Autodesk Fusion 360 part; units mm, degrees
(part 2 of 2)
ref_plane "WorkPlane2" through (-5.075, 0, 0) normal (1, 0, 0) x (0, 1, 0) in component "Factory radio brackets (placeholder)"
sketch "Sketch2 (13)" plane through (-5.075, 0, 0) normal (1, 0, 0) x (0, 0, -1) in component "Factory radio brackets (placeholder)"
  line L0 (42, 104.75) -> (34, 104.75)
  arc A0 (34, 110.25) -> (34, 104.75) centre (34, 107.5) ccw
  line L1 (34, 110.25) -> (42, 110.25)
  arc A1 (42, 104.75) -> (42, 110.25) centre (42, 107.5) ccw
  line L2 (42, 129.75) -> (34, 129.75)
  arc A2 (34, 135.25) -> (34, 129.75) centre (34, 132.5) ccw
  line L3 (34, 135.25) -> (42, 135.25)
  arc A3 (42, 129.75) -> (42, 135.25) centre (42, 132.5) ccw
  line L4 (42, 169.75) -> (34, 169.75)
  arc A4 (34, 175.25) -> (34, 169.75) centre (34, 172.5) ccw
  line L5 (34, 175.25) -> (42, 175.25)
  arc A5 (42, 169.75) -> (42, 175.25) centre (42, 172.5) ccw
  line L6 (42, 194.75) -> (34, 194.75)
  arc A6 (34, 200.25) -> (34, 194.75) centre (34, 197.5) ccw
  line L7 (34, 200.25) -> (42, 200.25)
  arc A7 (42, 194.75) -> (42, 200.25) centre (42, 197.5) ccw
extrude "Extrude2'''" cut sketch "Sketch2 (13)" along normal mid plane 3.6 bodies 18 in component "Factory radio brackets (placeholder)"
ref_plane "WorkPlane3" through (176.525, 0, 0) normal (1, 0, 0) x (0, 1, 0) in component "Factory radio brackets (placeholder)"
sketch "Sketch3 (10)" plane through (176.525, 0, 0) normal (1, 0, 0) x (0, 0, -1) in component "Factory radio brackets (placeholder)"
  line L0 (70, 87) -> (70, 218)
  arc A0 (70, 218) -> (68, 220) centre (68, 218) ccw
  line L1 (68, 220) -> (20, 220)
  arc A1 (20, 220) -> (18, 218) centre (20, 218) ccw
  line L2 (18, 218) -> (18, 87)
  arc A2 (18, 87) -> (20, 85) centre (20, 87) ccw
  line L3 (20, 85) -> (68, 85)
  arc A3 (68, 85) -> (70, 87) centre (68, 87) ccw
extrude "Extrude3" add sketch "Sketch3 (10)" along normal mid plane 1.6 separate body makes body 19 in component "Factory radio brackets (placeholder)"
ref_plane "WorkPlane4" through (176.525, 0, 0) normal (1, 0, 0) x (0, 1, 0) in component "Factory radio brackets (placeholder)"
sketch "Sketch4 (10)" plane through (176.525, 0, 0) normal (1, 0, 0) x (0, 0, -1) in component "Factory radio brackets (placeholder)"
  line L0 (42, 104.75) -> (34, 104.75)
  arc A0 (34, 110.25) -> (34, 104.75) centre (34, 107.5) ccw
  line L1 (34, 110.25) -> (42, 110.25)
  arc A1 (42, 104.75) -> (42, 110.25) centre (42, 107.5) ccw
  line L2 (42, 129.75) -> (34, 129.75)
  arc A2 (34, 135.25) -> (34, 129.75) centre (34, 132.5) ccw
  line L3 (34, 135.25) -> (42, 135.25)
  arc A3 (42, 129.75) -> (42, 135.25) centre (42, 132.5) ccw
  line L4 (42, 169.75) -> (34, 169.75)
  arc A4 (34, 175.25) -> (34, 169.75) centre (34, 172.5) ccw
  line L5 (34, 175.25) -> (42, 175.25)
  arc A5 (42, 169.75) -> (42, 175.25) centre (42, 172.5) ccw
  line L6 (42, 194.75) -> (34, 194.75)
  arc A6 (34, 200.25) -> (34, 194.75) centre (34, 197.5) ccw
  line L7 (34, 200.25) -> (42, 200.25)
  arc A7 (42, 194.75) -> (42, 200.25) centre (42, 197.5) ccw
extrude "Extrude4" cut sketch "Sketch4 (10)" along normal mid plane 3.6 bodies 19 in component "Factory radio brackets (placeholder)"
component "Dash panel" placed x (1, 0, 0) y (0, 1, 0) z (0, 0, 1) at (0, 0, 0)
component "Screen carrier" placed x (1, 0, 0) y (0, 1, 0) z (0, 0, 1) at (0, 0, 0)
component "Volume knob" placed x (1, 0, 0) y (0, 1, 0) z (0, 0, 1) at (0, 0, 0)
component "Adapter plate lower left" placed x (1, 0, 0) y (0, 1, 0) z (0, 0, 1) at (0, 0, 0)
component "Adapter plate upper left" placed x (1, 0, 0) y (0, 1, 0) z (0, 0, 1) at (0, 0, 0)
component "Adapter plate lower right" placed x (1, 0, 0) y (0, 1, 0) z (0, 0, 1) at (0, 0, 0)
component "Adapter plate upper right" placed x (1, 0, 0) y (0, 1, 0) z (0, 0, 1) at (0, 0, 0)
component "Pi case" placed x (1, 0, 0) y (0, 1, 0) z (0, 0, 1) at (0, 0, 0)
component "Amp plate" placed x (1, 0, 0) y (0, 1, 0) z (0, 0, 1) at (0, 0, 0)
component "Screen (reference)" placed x (1, 0, 0) y (0, 1, 0) z (0, 0, 1) at (0, 0, 0)
component "Raspberry Pi 5 + DAC (reference)" placed x (1, 0, 0) y (0, 1, 0) z (0, 0, 1) at (0, 0, 0)
component "Amp (reference)" placed x (1, 0, 0) y (0, 1, 0) z (0, 0, 1) at (0, 0, 0)
component "Mean Well RSD-30G-5 (reference)" placed x (1, 0, 0) y (0, 1, 0) z (0, 0, 1) at (0, 0, 0)
component "Climate controls (space)" placed x (1, 0, 0) y (0, 1, 0) z (0, 0, 1) at (0, 0, 0)
component "Factory radio brackets (placeholder)" placed x (1, 0, 0) y (0, 1, 0) z (0, 0, 1) at (0, 0, 0)
equation "BajaCaseVersion = 7" comment "Marks this design as the Baja dash case; the script rebuilds it in place"
equation "OpeningWidth = 171.45 mm" comment "MEASURED (Caleb): bezel opening width, 6 3/4 in"
equation "OpeningHeight = 222.25 mm" comment "MEASURED (Caleb): bezel opening height, 8 3/4 in"
equation "CornerRadiusTopLeft = 15 mm" comment "MEASURED (Caleb, re-measured after the first test print)"
equation "CornerRadiusTopRight = 3 mm" comment "MEASURED (Caleb, re-measured after the first test print)"
equation "CornerClearance = 0.5 mm" comment "DESIGN: the panel's top corners are this much rounder than the opening's, so they never bind"
equation "ClimateGap = 82.55 mm" comment "MEASURED (Caleb): the climate controls fill the bottom 3 1/4 in of the opening (6 3/4 in wide)"
equation "BezelReturnDepth = 20 mm" comment "UNKNOWN: how far the bezel walls reach behind the panel; the adapters step out behind them"
equation "BracketSeparation = 180 mm" comment "ESTIMATED: inside face to inside face of the factory brackets (radio width); 180 is a common DIN width, not verified for the Baja"
equation "FactoryBracketUpperY = 185 mm" comment "UNKNOWN: middle of the upper adapter screws, above the bottom of the opening"
equation "FactoryBracketLowerY = 120 mm" comment "UNKNOWN: middle of the lower adapter screws, above the bottom of the opening"
equation "FactoryBracketHoleSpacing = 25 mm" comment "UNKNOWN: up-and-down spacing of the two screws each adapter takes"
equation "FactoryHoleDiameter = 5.5 mm" comment "ESTIMATED: M5 clearance; Subaru screw 045005160 reads as M5 x 16 by its part-number pattern"
equation "FactoryBracketThickness = 1.6 mm" comment "UNKNOWN: steel thickness of the factory bracket (reference model only)"
equation "PanelThickness = 12.7 mm" comment "DESIGN (Caleb): 1/2 in"
equation "FitGap = 0 mm" comment "DESIGN: 0 = exactly the measured opening; add 0.2-0.4 per side if the test print is tight"
equation "PanelBottomRadius = 0 mm" comment "MEASURED (Caleb): the opening's bottom corners are square"
equation "FrameEdgeDepth = 10 mm" comment "MEASURED (Caleb): the silver frame is 10 mm thick at the opening's edge; the panel's front part is this deep"
equation "LipSide = 3 mm" comment "MEASURED (Caleb): behind the frame the panel is this much wider on the left and right, so the frame holds it"
equation "LipTop = 3 mm" comment "MEASURED (Caleb): the same 3 mm lip along the top edge"
equation "LipRadiusTopLeft = 0 mm" comment "DESIGN (Caleb): the lip's top-left corner is square; the top-right follows the rounded corner"
equation "AdapterPlateThickness = 4 mm" comment "DESIGN: adapter plate wall (ASA, carries the M5 screws)"
equation "AdapterHeight = 50 mm" comment "DESIGN: height of each of the four adapter plates"
equation "AdapterSideLength = 40 mm" comment "DESIGN: front-to-back length of the slotted side wall"
equation "AdapterSlotLength = 24 mm" comment "DESIGN: front-to-back adjustment in the side slots"
equation "ScreenWidth = 194 mm" comment "VERIFIED: Waveshare 8DP-CAPLCD drawing; Caleb's caliper check of the holes matches it"
equation "ScreenHeight = 119 mm" comment "VERIFIED: Waveshare 8DP-CAPLCD drawing"
equation "ScreenDepth = 4.8 mm" comment "VERIFIED: glass + LCD, Waveshare drawing"
equation "ScreenBackDepth = 11.39 mm" comment "VERIFIED: glass front to the back of the mounting nuts, Waveshare drawing"
equation "ScreenMountHoleSpacing = 58 mm" comment "VERIFIED: Raspberry Pi hole pattern, side to side (Waveshare drawing)"
equation "ScreenMountHoleSpacingV = 49 mm" comment "VERIFIED: Raspberry Pi hole pattern, up and down"
equation "ScreenMountOffsetX = -12.21 mm" comment "VERIFIED: hole pattern centre is 12.2 mm left of the glass centre, seen from the front (Waveshare drawing; Caleb measured 12.8)"
equation "ScreenMountOffsetY = -3.21 mm" comment "VERIFIED: 3.2 mm below the glass centre (Waveshare drawing; Caleb measured 3.9)"
equation "ScreenOverhangTop = 5.5 mm" comment "DESIGN (Caleb): top of the screen stands this far above the opening"
equation "ScreenStandoffHeight = 6 mm" comment "DESIGN (Caleb): posts from the panel face to the back of the screen, 6 at most"
equation "ScreenPostDiameter = 8 mm" comment "DESIGN: the carrier's screen posts"
equation "DisplayTiltAngle = 0 deg" comment "DESIGN: + leans the screen back by shortening the top posts; keep it small (0 to 4)"
equation "CableClearance = 6 mm" comment "DESIGN: room around the plugs in the panel notch"
equation "PlugAreaLeft = -40 mm" comment "VERIFIED: left end of the USB-C/HDMI/USB sockets from the glass centre, seen from the front (Waveshare drawing)"
equation "PlugAreaRight = 14 mm" comment "VERIFIED: right end of the sockets from the glass centre (Waveshare drawing)"
equation "PlugAreaBottom = 33 mm" comment "VERIFIED: the board's top edge, where the plugs go in, above the glass centre (Waveshare drawing; HDMI faces up, Caleb)"
equation "KnobX = 25 mm" comment "DESIGN (Caleb): driver side"
equation "KnobY = 93.3 mm" comment "DESIGN: centred between the climate controls and the bottom of the screen"
equation "KnobDiameter = 19 mm" comment "DESIGN: 3/4 in; the strip between the climate controls and the screen is about 24.5 mm tall"
equation "KnobHeight = 18 mm" comment "DESIGN: fits a 15 or 20 mm encoder shaft"
equation "EncoderWall = 2.5 mm" comment "DESIGN: panel left in front of the encoder so its nut reaches"
equation "EncoderCollarHole = 7.4 mm" comment "ESTIMATED: EC11 threaded collar is M7"
equation "EncoderPocket = 15 mm" comment "MEASURED (Caleb): square pocket for the encoder body, 15 x 15"
equation "ShaftDiameter = 6.1 mm" comment "MEASURED (Caleb): 6 mm shaft"
equation "ShaftFlat = 4.6 mm" comment "ESTIMATED: D shaft, 4.5 mm across the flat"
equation "PiX = 43.2 mm" comment "DESIGN: left edge of the Pi board"
equation "PiY = 110 mm" comment "DESIGN: bottom edge of the Pi board"
equation "PiStandoffHeight = 6 mm" comment "DESIGN"
equation "PiCaseWall = 2 mm" comment "DESIGN: wall of the Pi case"
equation "PiCaseHeight = 25 mm" comment "DESIGN: wall height from the case floor; the top stays open for the DAC HAT and airflow"
equation "PiStackHeight = 34 mm" comment "ESTIMATED: Pi + active cooler + DAC HAT, for the clearance check"
equation "AmpBoardWidth = 125 mm" comment "ESTIMATED: the amp board (Taidacent XH-M180), long side: the hole spacing plus 3.5 mm each side; measure"
equation "AmpBoardHeight = 83 mm" comment "ESTIMATED: the amp board, short side: the hole spacing plus 3.5 mm each side; measure"
equation "AmpHoleSpacingX = 118 mm" comment "MEASURED (Caleb): the amp board's mounting holes, centre to centre along the long side"
equation "AmpHoleSpacingY = 76 mm" comment "MEASURED (Caleb): the amp board's mounting holes, centre to centre along the short side"
equation "AmpTotalHeight = 29 mm" comment "ESTIMATED: the amp's height with its heatsink, from the seller's listing"
equation "AmpStandoffHeight = 33 mm" comment "DESIGN: posts under the amp board; the Mean Well sits under it on the same plate, with 4 mm to spare"
equation "AmpPlateThickness = 3 mm" comment "DESIGN"
equation "AmpClearance = 5 mm" comment "DESIGN: air gap between the top of the Pi stack (DAC HAT) and the amp plate"
equation "AmpPostSize = 8 mm" comment "DESIGN: the four square posts on the Pi case that hold the amp plate"
equation "MeanWellLength = 113 mm" comment "VERIFIED: Mean Well RSD-30 datasheet, case 253A"
equation "MeanWellWidth = 60 mm" comment "VERIFIED: Mean Well RSD-30 datasheet"
equation "MeanWellHeight = 25 mm" comment "VERIFIED: Mean Well RSD-30 datasheet"
equation "MeanWellHoleSpacingX = 105 mm" comment "VERIFIED: its four 3.5 mm holes, centre to centre along the long side (datasheet)"
equation "MeanWellHoleSpacingY = 52 mm" comment "VERIFIED: the same holes along the short side (datasheet)"
equation "MeanWellBossHeight = 4 mm" comment "DESIGN: bosses it stands on, deep enough for the M3 inserts"
equation "CarrierThickness = 3 mm" comment "DESIGN: the carrier plate; the pocket in the panel is this deep, so it sits flush"
equation "CarrierScrewLength = 8 mm" comment "DESIGN: M2.5 screws from the back of the carrier into the screen; the counterbore depth follows"
equation "CarrierLockScrewX = 40 mm" comment "DESIGN: the two M3 lock screws below the screen, this far left and right of centre"
equation "CarrierTabDrop = 13 mm" comment "DESIGN: how far the carrier reaches below the screen, for the lock screws"
equation "CarrierHookInset = 18 mm" comment "DESIGN: hook centres in from the carrier edges, clear of the cable notch"
named bodies: "Dash panel", "Screen carrier", "Volume knob", "Adapter plate lower left", "Adapter plate upper left", "Adapter plate lower right", "Adapter plate upper right", "Pi case", "Amp plate"
